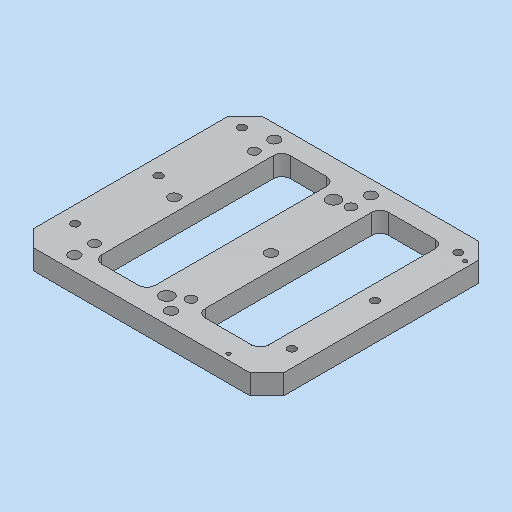
# Autodesk Inventor part: MM0948AN002_G01_114
Saved by Autodesk Inventor 2023.3 (Build 273359000, 359)
## iProperties
RuleStatus: InUse
Created: 2023-04-28
Part Number: MM0948AN002_G01_114
Material: 3.3547 AlMg4,5Mn0,7 - AW 5083
Description: =<RBPARTNOTITLE2>
Document SubType Name: Modeling
Designer: ric7an
Mass: 378.182 g
Surface Area: 424.044 cm^2
Volume: 142.174 cm^3
Density: 2.66 g/cm^3
Appearance: Aluminium AnP
AnP_Kategorie: 1
AnP_Material: =<Material>
MaxAbmaße: 12 x 137 x 150 (FM)
AnP_TemplVers: 20200821
RBDOCUMENTTYPE: DRF
RBDOCUMENTVERSION: 00
RBDRAWINGMAINSCALE: 1:1
RBDRAWINGMISSINGSPEC: --
RBDRAWINGVOLUME: --
RBDSV1: 0850
RBGBEDGESIN1: +0,5
RBGBEDGESIN2: +0,2
RBGBEDGESOUT1: -0,3
RBGBEDGESOUT2: -0,1
RBMATERIAL: =<Material>
RBMATMEETS: --
RBMATNO: =<Part Number>
RBPARTMADEOF: 12 x 137 x 150 (FM)
RBPARTNO: SIEHE MNR
RBPARTNOTITLE1: manufactured part
RBPARTNOTITLE2: Anfertigungsteil
RBPARTSAFETYINDICATOR: --
RBSURFACE: anodised colourless
RBSURFACE2: eloxiert farblos
RBZEDGESNORM: ISO13715:2002-06
RBZGENDIMCLASS: m
RBZGENDIMNORM: ISO 2768-1:1989-11
RBZGENGEOCLASS: H
RBZGENGEONORM: ISO 2768-2:1989-11
RBZSURFACENORM: ISO13D2:2002-02
RBZTOLERANCENORM: ISO 14405-1:2010-12
Author: ric7an
Keywords: =<RBPARTMADEOF>
Comments: =<RBSURFACE2>
Revision Number: 01
Autodesk Inventor part; units mm, degrees
ref_plane "YZ Plane" through (0, 0, 0) normal (1, 0, 0) x (0, 1, 0)
ref_plane "XZ Plane" through (0, 0, 0) normal (0, 1, 0) x (-1, 0, 0)
ref_plane "XY Plane" through (0, 0, 0) normal (0, 0, 1) x (1, 0, 0)
sketch "Skizze1" plane through (0, 0, 0) normal (0, 0, 1) x (1, 0, 0)
  line L0 (-75, 137) -> (75, 137)
  line L1 (75, 137) -> (75, 0)
  line L2 (75, 0) -> (-75, 0)
  line L3 (-75, 0) -> (-75, 137)
  line L4 (0, 164.4) -> (0, -27.4) projected
  line L5 (-105, 0) -> (105, 0) projected
  point P0 (0, 0)
  dimension "d0" = 150
  dimension "d1" = 137
  constraints: 8 end point, 2 parallel, 1 collinear, 1 horizontal, 1 perpendicular, 1 other
  measures "d0" distance of L0.start L0.end
  measures "d1" distance of L0.end L1.end
extrude "Extrusion1" add sketch "Skizze1" along normal blind 12
sketch "Skizze2" plane through (0, 0, 0) normal (0, 0, -1) x (-1, 0, 0)
  line L0 (0, -27.4) -> (0, 164.4) projected
  line L1 (-105, 0) -> (105, 0) projected
  line L2 (-75, 0) -> (-75, 137) projected
  point P0 (0, 0)
  point P1 (-65, 125)
  point P2 (-65, 75)
  point P3 (-65, 25)
  point P4 (65, 125)
  point P5 (65, 75)
  point P6 (65, 25)
  dimension "d4" = 100
  dimension "d6" = 50
  dimension "d7" = 25
  dimension "d9" = 10
  constraints: 3 symmetric about line, 2 vertical alignment
  measures "d4" distance of point (-65, 25) point (-65, 125)
  measures "d6" distance of point (-65, 25) point (-65, 75)
  measures "d7" distance from line of L1 point (-65, 25)
  measures "d9" distance from line of point (-65, 125) L2
hole "Bohrung1" at (65, 125, 0) at (65, 75, 0) at (65, 25, 0) at (-65, 125, 0) at (-65, 75, 0) at (-65, 25, 0) direction (0, 0, 1) diameter 4.917 end through all thread size "M6x1" designation "M6" class "6H" standard "ISO Metric profile"
sketch "Skizze3" plane through (0, 0, 0) normal (0, 0, -1) x (-1, 0, 0)
  line L0 (75, 0) -> (-75, 0) projected
  line L1 (75, 137) -> (75, 0) projected
  point P0 (0, 0)
  point P1 (-9, 8.5)
  point P2 (-9, 68.5)
  point P3 (-9, 128.5)
  point P4 (49, 8.5)
  point P5 (49, 68.5)
  point P6 (49, 128.5)
  dimension "d17" = 120
  dimension "d18" = 60
  dimension "d19" = 8.5
  dimension "d20" = 26
  dimension "d21" = 58
  constraints: 4 vertical alignment, 3 horizontal alignment
  measures "d17" distance of point (49, 8.5) point (49, 128.5)
  measures "d18" distance of point (49, 8.5) point (49, 68.5)
  measures "d19" distance from line of L0 point (49, 8.5)
  measures "d20" distance from line of L1 point (49, 8.5)
  measures "d21" distance of point (49, 8.5) point (-9, 8.5)
hole "Bohrung2" at (9, 8.5, 0) at (9, 68.5, 0) at (9, 128.5, 0) at (-49, 8.5, 0) at (-49, 68.5, 0) at (-49, 128.5, 0) direction (0, 0, 1) diameter 6.6 end through all counterbore diameter 11 counterbore depth 6.8 clearance for "Inbusschraube ISO 4762  versenkt" size "M6" standard "ISO"
sketch "Skizze4" plane through (0, 0, 0) normal (0, 0, -1) x (-1, 0, 0)
  circle A0 centre (-9, 128.5) radius 5.5 projected
  circle A1 centre (49, 128.5) radius 5.5 projected
  circle A2 centre (-9, 8.5) radius 5.5 projected
  circle A3 centre (49, 8.5) radius 5.5 projected
  circle A4 centre (-9, 8.5) radius 3.3 projected
  point P0 (0, 0)
  point P1 (-9, 116.5)
  point P2 (49, 116.5)
  point P3 (49, 20.5)
  point P4 (-9, 20.5)
  dimension "d29" = 12
  dimension "d30" = 12
  constraints: 4 vertical alignment, 2 horizontal alignment
  measures "d29" distance of A0.centre point (-9, 116.5)
  measures "d30" distance of A4.centre point (-9, 20.5)
hole "Bohrung3" at (9, 116.5, 0) at (-49, 116.5, 0) at (-49, 20.5, 0) at (9, 20.5, 0) direction (0, 0, 1) diameter 6 end through all
sketch "Skizze5" plane through (0, 0, 0) normal (0, 0, -1) x (-1, 0, 0)
  line L0 (75, 0) -> (-75, 0) projected
  line L1 (75, 137) -> (75, 0) projected
  point P0 (0, 0)
  point P1 (0, 115)
  point P2 (0, 15)
  dimension "d38" = 100
  dimension "d39" = 15
  dimension "d40" = 75
  constraints: 1 vertical alignment
  measures "d38" distance of point (0, 15) point (0, 115)
  measures "d39" distance from line of L0 point (0, 15)
  measures "d40" distance from line of L1 point (0, 15)
hole "Bohrung4" at (0, 115, 0) at (0, 15, 0) direction (0, 0, 1) diameter 8 end through all
sketch "Skizze6" plane through (0, 0, 12) normal (0, 0, 1) x (1, 0, 0)
  line L0 (-75, 0) -> (75, 0) projected
  line L1 (75, 0) -> (75, 137) projected
  point P0 (0, 0)
  point P1 (71.5, 122.5)
  point P2 (48.5, 3.5)
  dimension "d48" = 119
  dimension "d49" = 23
  dimension "d50" = 3.5
  dimension "d51" = 26.5
  measures "d48" vertical distance of point (48.5, 3.5) point (71.5, 122.5)
  measures "d49" horizontal distance of point (48.5, 3.5) point (71.5, 122.5)
  measures "d50" distance from line of L0 point (48.5, 3.5)
  measures "d51" distance from line of L1 point (48.5, 3.5)
hole "Bohrung5" at (71.5, 122.5, 12) at (48.5, 3.5, 12) direction (0, 0, -1) diameter 2.459 end through all thread size "M3x0.5" designation "M3" class "6H" standard "ISO Metric profile"
sketch "Skizze7" plane through (0, 0, 12) normal (0, 0, 1) x (1, 0, 0)
  line L0 (-41, 125) -> (-9, 125)
  line L1 (-9, 125) -> (-9, 12)
  line L2 (-9, 12) -> (-41, 12)
  line L3 (-41, 12) -> (-41, 125)
  line L4 (18, 125) -> (56, 125)
  line L5 (56, 125) -> (56, 15)
  line L6 (56, 15) -> (18, 15)
  line L7 (18, 15) -> (18, 125)
  line L8 (0, 164.4) -> (0, -27.4) projected
  line L9 (-75, 0) -> (75, 0) projected
  line L10 (75, 137) -> (-75, 137) projected
  point P0 (0, 0)
  dimension "d59" = 9
  dimension "d60" = 32
  dimension "d61" = 12
  dimension "d62" = 12
  dimension "d63" = 12
  dimension "d64" = 15
  dimension "d65" = 18
  dimension "d66" = 38
  constraints: 16 end point, 4 parallel, 2 horizontal, 2 perpendicular
  measures "d59" distance between parallel lines of L1 L8
  measures "d60" distance of L0.start L0.end
  measures "d61" distance between parallel lines of L9 L2
  measures "d62" distance between parallel lines of L0 L10
  measures "d63" distance between parallel lines of L10 L4
  measures "d64" distance between parallel lines of L9 L6
  measures "d65" distance between parallel lines of L8 L7
  measures "d66" distance of L4.start L4.end
extrude "Extrusion2" cut sketch "Skizze7" against normal through all
chamfer "Fase1" distance 10 angle 45 4 edges at (-75, 137, 6) (75, 137, 6) (75, 0, 6) (-75, 0, 6)
fillet "Rundung1" radius 5 8 edges at (-41, 125, 6) (-9, 125, 6) (-9, 12, 6) (-41, 12, 6) (18, 15, 6) (18, 125, 6) (56, 125, 6) (56, 15, 6)
equation "\"d18\" = 0.5 * d17"
equation "\"d61\" = d62"
equation "\"d63\" = d62"
